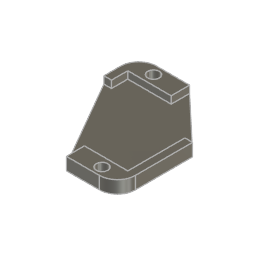
Servo-Bracket-24x24mm (Autodesk Fusion 360 design; units mm, degrees)
part number: 2026-04-19-10-50-48-421
Autodesk Fusion 360 part; units mm, degrees
sketch "Sketch1" plane through (0, 0, 0) normal (0, 0, 1) x (1, 0, 0)
  line L0 (11.125, 11.125) -> (-11.125, 11.125)
  line L1 (-11.125, -11.125) -> (11.125, -11.125)
  line L2 (-11.125, 6.975) -> (-15.975, 6.975)
  line L3 (-15.975, 6.975) -> (-15.975, 4.325)
  line L4 (-15.975, 4.325) -> (-11.125, 4.325)
  line L5 (15.975, 6.975) -> (11.125, 6.975)
  line L6 (11.125, 4.325) -> (15.975, 4.325)
  line L7 (15.975, 6.975) -> (15.975, 4.325)
  line L8 (-11.125, 11.125) -> (-11.125, 6.975)
  line L9 (-11.125, 4.325) -> (-11.125, -11.125)
  line L10 (11.125, -11.125) -> (11.125, 4.325)
  line L11 (11.125, 6.975) -> (11.125, 11.125)
  line L12 (-14.125, -11.125) -> (-14.125, 4.325)
  line L13 (-14.125, 6.975) -> (-14.125, 12.125)
  line L14 (-14.125, -11.125) -> (-14.125, -14.125)
  line L15 (-14.125, -14.125) -> (0, -14.125)
  line L16 (14.125, -14.125) -> (14.125, 4.325)
  line L17 (14.125, 11.1) -> (14.125, 6.975)
  line L18 (14.125, 11.1) -> (11.125, 11.125)
  line L19 (11.125, 6.975) -> (11.125, 4.325)
  line L20 (-11.125, 6.975) -> (-11.125, 4.325)
  line L21 (-14.125, 12.125) -> (-14.125, 17.125)
  line L22 (-14.125, 17.125) -> (0, 17.125)
  line L23 (0, 17.125) -> (0, 11.125)
  line L24 (0, -14.125) -> (0, -17)
  line L25 (0, -17) -> (14.125, -17)
  line L26 (14.125, -17) -> (14.125, -14.125)
  circle A0 centre (-7.5, 14.625) radius 1.6
  circle A1 centre (7.5, -14.625) radius 1.6
  line L27 (12, 12) -> (-12, 12)
  line L28 (-12, 12) -> (-12, -12)
  line L29 (-12, -12) -> (12, -12)
  line L30 (12, -12) -> (12, 12)
  line L31 (12, 12) -> (-12, -12) construction
  line L32 (-12, 12) -> (12, -12) construction
  line L33 (-14.125, 7.487) -> (-11.125, 7.487)
  line L34 (14.125, 3.8) -> (11.125, 3.8)
  line L35 (0, -17) -> (-14.125, 7.487)
  line L36 (0, 17.125) -> (14.125, 3.8)
  line L37 (0, -14.125) -> (0, -12)
  dimension "d11" = 3
  dimension "d15" = 5
  dimension "d34" = 24
  dimension "d35" = 24
  dimension "d43" = 29.25
  dimension "d44" = 15
  constraint horizontal L0
  constraint perpendicular L0 L8
  constraint parallel L0 L1
  constraint parallel L8 L11
  constraint perpendicular L2 L8
  constraint perpendicular L2 L3
  constraint perpendicular L4 L9
  constraint perpendicular L6 L7
  constraint collinear L8 L9
  constraint collinear L10 L11
  constraint coincident L4 L12.end
  constraint perpendicular L4 L12
  constraint coincident L2 L13.start
  constraint perpendicular L2 L13
  constraint coincident L6 L16.end
  constraint perpendicular L6 L16
  constraint coincident L5 L17.end
  constraint perpendicular L5 L17
  constraint perpendicular L6 L19
  constraint perpendicular L21 L22
  constraint midpoint L0 L23.end
  constraint perpendicular L0 L23
  constraint perpendicular L15 L24
  constraint perpendicular L24 L25
  constraint perpendicular L15 L26
  constraint horizontal L27
  constraint perpendicular L27 L28
  constraint parallel L27 L29
  constraint parallel L28 L30
  constraint coincident L31 origin
  constraint coincident L32 origin
  constraint coincident L13 L33.start
  constraint coincident L8 L33.end
  constraint perpendicular L8 L33
  constraint coincident L16 L34.start
  constraint coincident L10 L34.end
  constraint perpendicular L10 L34
  constraint midpoint L29 L37.end
  constraint perpendicular L29 L37
  measures "d11" distance of L12.start L14.end
  measures "d15" distance of L13.end L21.end
  measures "d34" distance of L28.end L29.end
  measures "d35" distance of L27.end L28.end
  measures "d43" vertical distance of A0.centre A1.centre
  measures "d44" horizontal distance of A0.centre A1.centre
extrude "Extrude1" add sketch "Sketch1" along normal blind 1.5 contours L0 L1 L8 L9 L10 L19 L20 L35 L36 | L0 L23 L27 L36 | L0 L8 L23 L27 L28 L33 | L23 L27 L36 | L2 L8 L28 L33 | L6 L19 L30 L36 | L2 L4 L20 L28 | L2 L28 L33 L35 | L6 L10 L30 L34 | L6 L30 L36 | L2 L4 L28 L35 | L4 L9 L28 L35 | L6 L30 L34 L36 | L1 L10 L29 L30 L34 L35 | L4 L28 L35 | L15 L29 L35 L37 | L15 L24 L35 makes body 1
extrude "Extrude6" add sketch "Sketch1" along normal blind 3.5 separate body contours L13 L21 L22 L23 L27 L28 L33 | L16 L24 L25 L26 L29 L30 L34 L37 makes body 2 at (1.9667, -14.5417, 0) makes body 3 at (-1.9667, 14.5833, 0)
fillet "Fillet6" radius 5 2 edges at (14.125, -17, 1.75) (-14.125, 17.125, 1.75) on bodies 2 3
